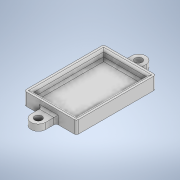
# Autodesk Inventor part: suport hx711
Saved by Autodesk Inventor 2022.6 (Build 266554000, 554)
## iProperties
Created: 2026-10-29
Part Number: suport hx711
Material: Generic
Document SubType Name: Modeling
Designer: Dragos Macovei
Density: 1 g/cm^3
Appearance: Default
Author: Dragos Macovei
Autodesk Inventor part; units mm, degrees
ref_plane "YZ Plane" through (0, 0, 0) normal (1, 0, 0) x (0, 1, 0)
ref_plane "XZ Plane" through (0, 0, 0) normal (0, 1, 0) x (-1, 0, 0)
ref_plane "XY Plane" through (0, 0, 0) normal (0, 0, 1) x (1, 0, 0)
sketch "Sketch1" plane through (0, 0, 0) normal (0, 1, 0) x (-1, 0, 0)
  line L0 (0, 0) -> (21, 0)
  line L1 (21, 0) -> (21, 34)
  line L2 (21, 34) -> (0, 34)
  line L3 (0, 34) -> (0, 0)
  line L4 (23, 36) -> (-2, 36)
  line L5 (-2, 36) -> (-2, -2)
  line L6 (-2, -2) -> (23, -2)
  line L7 (23, -2) -> (23, 36)
  dimension "d0" = 21
  dimension "d1" = 34
  dimension "d3" = 2
  dimension "d4" = 2
  dimension "d5" = 2
  dimension "d6" = 2
  constraints: 16 end point, 4 parallel, 2 horizontal, 2 perpendicular
  measures "d0" distance of L2.end L1.end
  measures "d1" distance of L1.end L0.end
  measures "d3" distance between parallel lines of L0 L6
  measures "d4" distance between parallel lines of L1 L7
  measures "d5" distance between parallel lines of L4 L2
  measures "d6" distance between parallel lines of L5 L3
extrude "Extrusion1" add sketch "Sketch1" along normal blind 6
sketch "Sketch2" plane through (0, 0, 0) normal (0, -1, 0) x (1, 0, 0)
  line L0 (2, 36) -> (2, -2) projected
  line L1 (-23, 36) -> (2, 36) projected
  line L2 (-23, -2) -> (-23, 36) projected
  line L3 (2, -2) -> (-23, -2) projected
  line L4 (0, 0) -> (0, 34) projected
  line L5 (-21, 0) -> (0, 0) projected
  line L6 (-21, 34) -> (-21, 0) projected
  line L7 (0, 34) -> (-21, 34) projected
extrude "Extrusion2" add sketch "Sketch2" against normal blind 2 contours L5 L6 L7 L4
fillet "Fillet1" radius 1 8 edges at (-21, 6, 17) (-10.5, 6, 0) (-10.5, 6, 34) (0, 6, 17) (-21, 2, 17) (-10.5, 2, 0) (-10.5, 2, 34) (0, 2, 17)
sketch "Sketch3" plane through (0, 0, 0) normal (0, -1, 0) x (1, 0, 0)
  line L0 (2, 36) -> (2, -2) projected
  line L1 (-23, 36) -> (2, 36) projected
  line L2 (-23, -2) -> (-23, 36) projected
  line L3 (2, -2) -> (-23, -2) projected
  circle A0 centre (-11.2155, 41) radius 1.75
  circle A1 centre (-11.2155, -7) radius 1.75
  circle A2 centre (-11.2155, 41) radius 3.5
  circle A3 centre (-11.2155, -7) radius 3.5
  line L4 (-7.7155, -7) -> (-7.7155, -2)
  line L5 (2, -2) -> (-23, -2) projected
  line L6 (-14.7155, -7) -> (-14.7155, -2)
  line L7 (-7.7155, 41) -> (-7.7155, 26.9156)
  line L8 (-14.7155, 41) -> (-14.7155, 22.8291)
  point P0 (0, 0)
  point P1 (-14.7155, -2)
  point P2 (-14.7155, 36)
  point P3 (-7.7155, 36)
  dimension "d12" = 3.5
  dimension "d13" = 3.5
  dimension "d14" = 5
  dimension "d15" = 5
  dimension "d16" = 7
  dimension "d17" = 7
  constraints: 8 end point, 4 centre point, 4 point on circle, 4 point on line, 2 coincident, 2 perpendicular, 1 vertical
  measures "d12" diameter of A1
  measures "d13" diameter of A0
  measures "d14" distance from line of L1 A0.centre
  measures "d15" distance from line of L3 A1.centre
  measures "d16" diameter of A2
  measures "d17" diameter of A3
extrude "Extrusion3" add sketch "Sketch3" against normal blind 3 contours L1 L8 A2 L7 | L4 A3 L6 L3 | A2 | A3
fillet "Fillet2" radius 1 10 edges at (-11.2155, 3, -2) (-11.2155, 3, 36) (-7.7155, 1.5, 36) (-14.7155, 1.5, 36) (-14.7155, 1.5, -2) (-7.7155, 1.5, -2) (2, 3, -2) (2, 3, 36) (-23, 3, -2) (-23, 3, 36)
equation "\"d13\" = d12"
equation "\"d17\" = d16"
body "Solid1"
